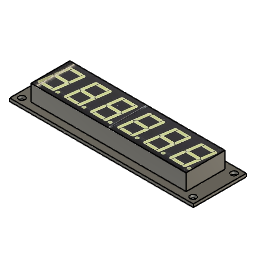
3PrinterDashboard (Autodesk Fusion 360 archive; units mm, degrees)
design "DRAWER_58_L_TM1637_6DIG"
Autodesk Fusion 360 part; units mm, degrees
sketch "Sketch1" plane through (0, 0, 0) normal (0, 0, 1) x (1, 0, 0)
  line L0 (-45, 13) -> (45, 13)
  line L1 (45, 13) -> (45, -13)
  line L2 (45, -13) -> (-45, -13)
  line L3 (-45, -13) -> (-45, 13)
  line L4 (-45, 13) -> (45, -13) construction
  line L5 (45, 13) -> (-45, -13) construction
  circle A0 centre (42, 10) radius 1.5
  line L6 (0, 2.5) -> (0, 20)
  circle A1 centre (-42, 10) radius 1.5
  line L7 (20, 0) -> (2.5, 0)
  circle A2 centre (-42, -10) radius 1.5
  circle A3 centre (42, -10) radius 1.5
  circle A4 centre (-43, 3.81) radius 0.508
  circle A5 centre (-43, 1.25) radius 0.508
  circle A6 centre (-43, -1.31) radius 0.508
  circle A7 centre (-43, -3.87) radius 0.508
  dimension "d1" = 90
  dimension "d2" = 26
  dimension "d9" = 3
  dimension "d10" = 10
  dimension "d11" = 42
  dimension "d12" = 1.016
  dimension "d13" = 2
  dimension "d14" = 3.81
  dimension "d17" = 0
  dimension "d18" = -7.68
  constraint horizontal L0
  constraint perpendicular L0 L1
  constraint parallel L0 L2
  constraint parallel L1 L3
  constraint coincident L4 origin
  constraint coincident L5 origin
  constraint symmetric A0 L6 A1
  constraint symmetric A0 L7 A3
  constraint symmetric A1 L7 A2
  measures "d1" distance of L1.end L2.end
  measures "d2" distance of L0.end L1.end
  measures "d9" diameter of A0
  measures "d10" vertical distance of origin A0.centre
  measures "d11" horizontal distance of origin A0.centre
  measures "d12" diameter of A4
  measures "d13" distance of L3 A4.centre
  measures "d14" vertical distance of origin A4.centre
extrude "Extrude1" add sketch "Sketch1" against normal blind 1.5
sketch "Sketch2" plane through (0, 0, 0) normal (0, 0, 1) x (-1, 0, 0)
  line L0 (45, 13) -> (-45, 13)
  line L1 (-45, 13) -> (-45, -13)
  line L2 (-45, -13) -> (45, -13)
  line L3 (45, -13) -> (45, 13)
  line L4 (38, -9.5) -> (-38, -9.5)
  line L5 (-38, -9.5) -> (-38, 9.5)
  line L6 (-38, 9.5) -> (38, 9.5)
  line L7 (38, 9.5) -> (38, -9.5)
  line L8 (38, -9.5) -> (-38, 9.5) construction
  line L9 (-38, -9.5) -> (38, 9.5) construction
  circle A0 centre (42, -10) radius 1.5
  circle A1 centre (-42, 10) radius 1.5
  circle A2 centre (-42, -10) radius 1.5
  circle A3 centre (42, 10) radius 1.5
  circle A4 centre (43, -3.81) radius 0.508
  circle A5 centre (43, 1.31) radius 0.508
  circle A6 centre (43, -1.25) radius 0.508
  circle A7 centre (43, 3.87) radius 0.508
  dimension "d5" = 76
  dimension "d6" = 19
  constraint horizontal L4
  constraint perpendicular L4 L5
  constraint parallel L4 L6
  constraint parallel L5 L7
  constraint coincident L8 origin
  constraint coincident L9 origin
  measures "d5" distance of L5.end L6.end
  measures "d6" distance of L4.end L5.end
extrude "Extrude2" add sketch "Sketch2" along normal blind 8 contours L4 L5 L6 L7
equation "d14 = 2.54 mm + ( 2.54 / 2 ) * 1 mm"

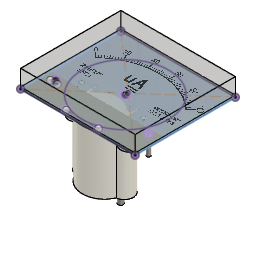
design "CUBE_034_100uA_Meter"
Autodesk Fusion 360 part; units mm, degrees
sketch "Circle" plane through (0, 0, 0) normal (0, 0, 1) x (1, 0, 0)
  circle A0 centre (0, 0) radius 24
  dimension "d1" = 48
  constraint coincident A0.centre origin
  measures "d1" diameter of A0
extrude "Extrude1" add sketch "Circle" against normal blind 3 makes body 1
sketch "PlasticBack" plane through (0, 0, -3) normal (0, 0, -1) x (1, 0, 0)
  circle A0 centre (0, 0) radius 24
  circle A1 centre (0, 11.5) radius 12.5
  circle A2 centre (-11, 11.5) radius 5
  line L0 (-16, 11.5) -> (-16, -22.7965) construction
  line L1 (0, -1.75) -> (0, -22.5)
  circle A3 centre (11, 11.5) radius 5
  dimension "d4" = 25
  dimension "d7" = 10
  dimension "d11" = 16
  constraint tangent A0 A1
  constraint horizontal A1.centre A2.centre
  constraint coincident A2 L0.start
  constraint vertical L0
  constraint tangent A2 L0
  constraint symmetric A2 L1 A3
  constraint vertical A0.centre A1.centre
  measures "d4" diameter of A1
  measures "d7" diameter of A2
  measures "d11" distance of A1.centre L0
extrude "Extrude2" add sketch "PlasticBack" along normal blind 33 contours A1 A2 A3 | A1 A3 | A1 A3 | A1 A2 | A1 A2 bodies 1
sketch "ShallowPlasticBack" plane through (0, 0, -3) normal (0, 0, -1) x (1, 0, 0)
  circle A0 centre (0, 0) radius 24
  arc A1 (11.4659, 16.4782) -> (0, 24) centre (0, 11.5) ccw
  arc A2 (11.4659, 6.5218) -> (11.4659, 16.4782) centre (11, 11.5) ccw
  arc A3 (-11.4659, 6.5218) -> (11.4659, 6.5218) centre (0, 11.5) ccw
  arc A4 (-11.4659, 16.4782) -> (-11.4659, 6.5218) centre (-11, 11.5) ccw
  arc A5 (0, 24) -> (-11.4659, 16.4782) centre (0, 11.5) ccw
  circle A6 centre (-14.4914, 11.5) radius 5.5
  circle A7 centre (0, 0) radius 24
  line L0 (0, -1.75) -> (0, -22.5)
  circle A8 centre (14.4914, 11.5) radius 5.5
  point P0 (0, 11.5)
  dimension "d12" = 11
  constraint horizontal A6.centre P0
  constraint tangent A6 A7
  constraint symmetric A6 L0 A8
  measures "d12" diameter of A6
extrude "Extrude3" add sketch "ShallowPlasticBack" along normal blind 8 contours A2 A8 | A4 A6 picked at (18.5596, 10.5861) picked at (-18.5268, 10.4492) bodies 1
sketch "Front" plane through (0, 0, 0) normal (0, 0, -1) x (1, 0, 0)
  line L0 (32, -29.5) -> (-32, -29.5)
  line L1 (-32, -29.5) -> (-32, 26.5)
  line L2 (-32, 26.5) -> (32, 26.5)
  line L3 (32, 26.5) -> (32, -29.5)
  line L4 (32, -29.5) -> (-32, 26.5) construction
  line L5 (-32, -29.5) -> (32, 26.5) construction
  circle A0 centre (0, 0) radius 24
  line L6 (9, 24) -> (-9, 24) construction
  circle A1 centre (0, 0) radius 24 construction
  point P0 (0, -1.5)
  dimension "d15" = 64
  dimension "d16" = 56
  dimension "d28" = 2.5
  constraint horizontal L0
  constraint perpendicular L0 L1
  constraint parallel L0 L2
  constraint parallel L1 L3
  constraint coincident L4 P0
  constraint coincident L5 P0
  constraint horizontal L6
  constraint tangent L6 A1
  measures "d15" distance of L1.end L2.end
  measures "d16" distance of L0.end L1.end
  measures "d28" distance of L2 L6
extrude "Extrude7" add sketch "Front" against normal blind 1 contours L0 L1 L2 L3 | A0 bodies 1
extrude "Extrude4" add sketch "Front" against normal blind 10 separate body contours L0 L1 L2 L3 | A0 makes body 2
sketch "MountingBolt" plane through (0, 0, 0) normal (0, 0, -1) x (1, 0, 0)
  line L0 (32, 26.5) -> (-32, 26.5)
  line L1 (-32, 26.5) -> (-32, -29.5)
  line L2 (-32, -29.5) -> (32, -29.5)
  line L3 (32, -29.5) -> (32, 26.5)
  circle A0 centre (-26, 13) radius 1
  line L4 (-27.9138, 14) -> (-24, 14) construction
  line L5 (9, 24) -> (-9, 24) construction
  dimension "d20" = 2
  dimension "d21" = 26
  dimension "d36" = 10
  constraint horizontal L4
  constraint tangent A0 L4
  measures "d20" diameter of A0
  measures "d21" horizontal distance of A0.centre origin
  measures "d36" distance of L4 L5
extrude "Extrude5" add sketch "MountingBolt" along normal blind 10 separate body contours A0 makes body 3
sketch "ConnectionBolt" plane through (0, 0, -36) normal (0, 0, -1) x (1, 0, 0)
  arc A0 (11.4659, 6.5218) -> (11.4659, 16.4782) centre (11, 11.5) ccw
  arc A1 (11.4659, 16.4782) -> (-11.4659, 16.4782) centre (0, 11.5) ccw
  arc A2 (-11.4659, 16.4782) -> (-11.4659, 6.5218) centre (-11, 11.5) ccw
  arc A3 (-11.4659, 6.5218) -> (11.4659, 6.5218) centre (0, 11.5) ccw
  circle A4 centre (-7.5, 10) radius 1.5
  line L0 (-32, 26.5) -> (32, 26.5)
  point P0 (-11, 11.5)
  dimension "d25" = 3
  dimension "d26" = 7.5
  dimension "d29" = 1.5
  measures "d25" diameter of A4
  measures "d26" horizontal distance of origin A4.centre
  measures "d29" vertical distance of A4.centre P0
extrude "Extrude6" add sketch "ConnectionBolt" along normal blind 7.75 separate body contours A4 makes body 4
mirror "Mirror1" about plane through (0, 0, 0) normal (1, 0, 0) of "Extrude5", "Extrude6" makes body 5 at (25.0012, -12.9502, -6.6667) makes body 6 at (6.0075, -9.8506, -41.1667)
sketch "CutOutline" plane through (0, 0, 0) normal (0, 0, -1) x (1, 0, 0)
  line L0 (32, 26.5) -> (-32, 26.5)
  line L1 (-32, 26.5) -> (-32, -29.5)
  line L2 (-32, -29.5) -> (32, -29.5)
  line L3 (32, -29.5) -> (32, 26.5)
  circle A0 centre (26, 13) radius 1
  circle A1 centre (-26, 13) radius 1
  circle A2 centre (0, 0) radius 24
